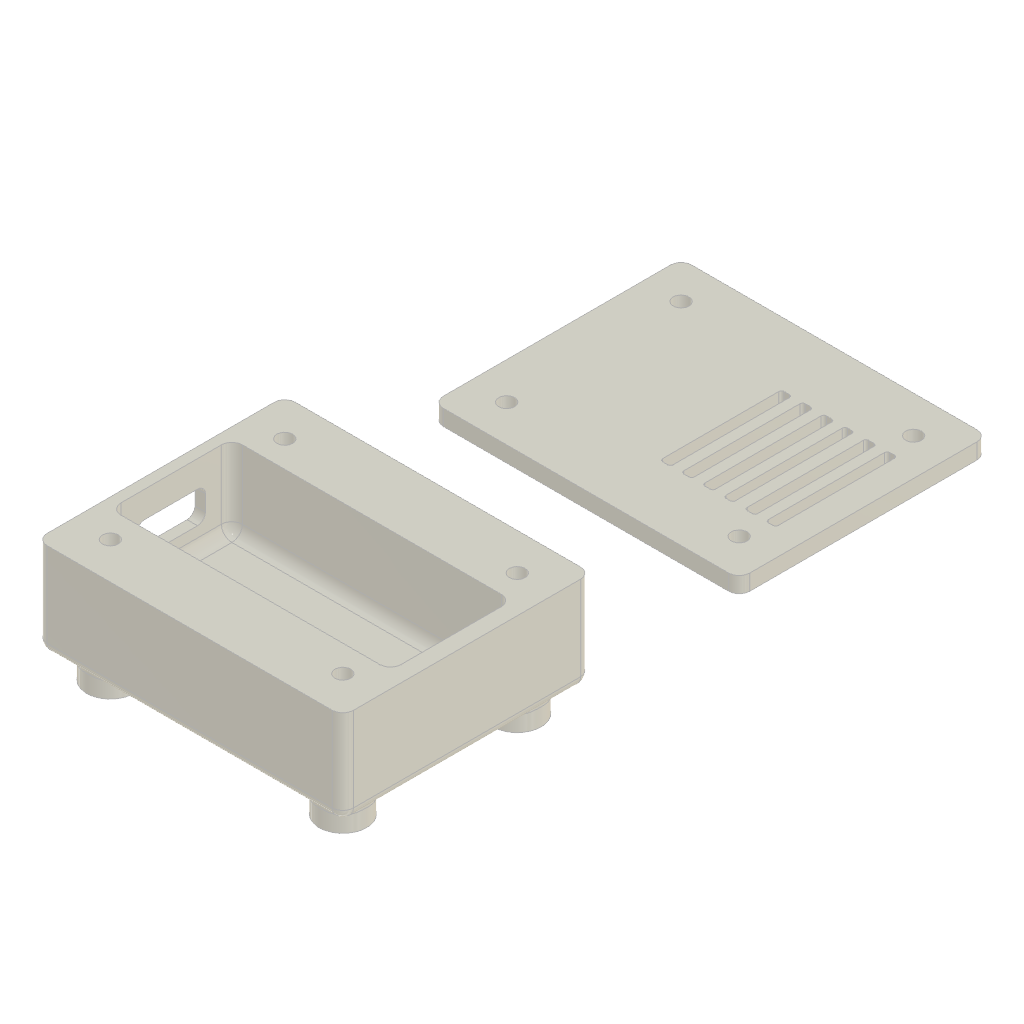
transmitter (Autodesk Fusion 360 design; units mm, degrees)
part number: 2026-10-18-01-48-49-370
Autodesk Fusion 360 part; units mm, degrees
sketch "Sketch1" plane through (0, 0, 0) normal (0, 0, 1) x (1, 0, 0)
  line L0 (20, 50) -> (73, 50)
  line L1 (73, 50) -> (73, 27)
  line L2 (73, 27) -> (20, 27)
  line L3 (20, 27) -> (20, 50)
  line L4 (20, 27) -> (20, 32) construction
  line L5 (20, 50) -> (20, 45) construction
  line L6 (20, 45) -> (18, 45)
  line L7 (18, 45) -> (18, 32)
  line L8 (18, 32) -> (20, 32)
  line L9 (20, 32) -> (20, 45)
  circle A0 centre (25, 55) radius 4.5
  circle A1 centre (25, 55) radius 3
  circle A2 centre (25, 55) radius 1.5
  line L10 (25, 55) -> (25, 50) construction
  line L11 (25, 27) -> (25, 22) construction
  line L12 (69, 50) -> (69, 55) construction
  line L13 (69, 27) -> (69, 22) construction
  circle A3 centre (69, 55) radius 1.5
  circle A4 centre (69, 55) radius 3
  circle A5 centre (69, 55) radius 4.5
  circle A6 centre (25, 22) radius 1.5
  circle A7 centre (69, 22) radius 1.5
  circle A8 centre (69, 22) radius 3
  circle A9 centre (69, 22) radius 4.5
  circle A10 centre (25, 22) radius 3
  circle A11 centre (25, 22) radius 4.5
  line L14 (18, 15) -> (76, 15)
  line L15 (76, 15) -> (76, 62)
  line L16 (76, 62) -> (18, 62)
  line L17 (18, 62) -> (18, 15)
  line L18 (73, 50) -> (70.8894, 50)
  line L19 (70.8894, 50) -> (70.8894, 27)
  line L20 (70.8894, 27) -> (73, 27)
  line L21 (73, 27) -> (73, 50)
  line L22 (70.8894, 27) -> (69, 27)
  line L23 (69, 27) -> (69, 50)
  line L24 (69, 50) -> (70.8894, 50)
  line L25 (70.8894, 50) -> (70.8894, 27)
  line L26 (69, 27) -> (67, 27)
  line L27 (67, 27) -> (67, 50)
  line L28 (67, 50) -> (69, 50)
  line L29 (69, 50) -> (69, 27)
  line L30 (67, 50) -> (65, 50)
  line L31 (65, 50) -> (65, 27)
  line L32 (65, 27) -> (67, 27)
  line L33 (67, 27) -> (67, 50)
  line L34 (65, 27) -> (62.7927, 27)
  line L35 (62.7927, 27) -> (62.7927, 50)
  line L36 (62.7927, 50) -> (65, 50)
  line L37 (65, 50) -> (65, 27)
  line L38 (62.7927, 50) -> (61, 50)
  line L39 (61, 50) -> (61, 27)
  line L40 (61, 27) -> (62.7927, 27)
  line L41 (62.7927, 27) -> (62.7927, 50)
  line L42 (61, 27) -> (59, 27)
  line L43 (59, 27) -> (59, 50)
  line L44 (59, 50) -> (61, 50)
  line L45 (61, 50) -> (61, 27)
  line L46 (59, 50) -> (57, 50)
  line L47 (57, 50) -> (57, 27)
  line L48 (57, 27) -> (59, 27)
  line L49 (59, 27) -> (59, 50)
  line L50 (57, 27) -> (55, 27)
  line L51 (55, 27) -> (55, 50)
  line L52 (55, 50) -> (57, 50)
  line L53 (57, 50) -> (57, 27)
  line L54 (55, 27) -> (53, 27)
  line L55 (53, 27) -> (53, 50)
  line L56 (53, 50) -> (55, 50)
  line L57 (55, 50) -> (55, 27)
  line L58 (53, 27) -> (51, 27)
  line L59 (51, 27) -> (51, 50)
  line L60 (51, 50) -> (53, 50)
  line L61 (53, 50) -> (53, 27)
  line L62 (51, 27) -> (49, 27)
  line L63 (49, 27) -> (49, 50)
  line L64 (49, 50) -> (51, 50)
  line L65 (51, 50) -> (51, 27)
  line L66 (25, 102) -> (25, 97) construction
  circle A12 centre (25, 97) radius 3
  line L67 (18, 137) -> (18, 90)
  line L68 (18, 120) -> (18, 107)
  circle A13 centre (25, 130) radius 3
  circle A14 centre (25, 130) radius 4.5
  circle A15 centre (25, 130) radius 1.5
  line L69 (18, 90) -> (76, 90)
  line L70 (18, 107) -> (20, 107)
  line L71 (20, 102) -> (20, 125)
  line L72 (20, 120) -> (18, 120)
  line L73 (20, 107) -> (20, 120)
  circle A16 centre (25, 97) radius 4.5
  line L74 (20, 125) -> (20, 120) construction
  line L75 (76, 137) -> (18, 137)
  circle A17 centre (25, 97) radius 1.5
  line L76 (20, 125) -> (73, 125)
  line L77 (73, 102) -> (20, 102)
  line L78 (25, 130) -> (25, 125) construction
  line L79 (73, 125) -> (70.8894, 125)
  line L80 (62.7927, 102) -> (62.7927, 125)
  line L81 (20, 102) -> (20, 107) construction
  circle A18 centre (69, 130) radius 4.5
  line L82 (67, 125) -> (69, 125)
  line L83 (69, 125) -> (69, 130) construction
  line L84 (51, 102) -> (51, 125)
  line L85 (57, 125) -> (57, 102)
  circle A19 centre (69, 130) radius 1.5
  line L86 (67, 102) -> (67, 125)
  circle A20 centre (69, 130) radius 3
  line L87 (62.7927, 125) -> (65, 125)
  line L88 (59, 102) -> (59, 125)
  line L89 (49, 102) -> (49, 125)
  line L90 (55, 102) -> (55, 125)
  line L91 (51, 125) -> (51, 102)
  line L92 (76, 90) -> (76, 137)
  line L93 (65, 102) -> (67, 102)
  line L94 (67, 125) -> (65, 125)
  line L95 (57, 102) -> (55, 102)
  circle A21 centre (69, 97) radius 1.5
  line L96 (73, 102) -> (73, 125)
  line L97 (65, 125) -> (65, 102)
  line L98 (69, 102) -> (67, 102)
  line L99 (69, 125) -> (70.8894, 125)
  circle A22 centre (69, 97) radius 4.5
  line L100 (55, 125) -> (57, 125)
  circle A23 centre (69, 97) radius 3
  line L101 (59, 125) -> (57, 125)
  line L102 (51, 125) -> (53, 125)
  line L103 (70.8894, 102) -> (69, 102)
  line L104 (53, 125) -> (53, 102)
  line L105 (55, 102) -> (53, 102)
  line L106 (61, 102) -> (59, 102)
  line L107 (49, 125) -> (51, 125)
  line L108 (70.8894, 125) -> (70.8894, 102)
  line L109 (65, 102) -> (62.7927, 102)
  line L110 (59, 125) -> (61, 125)
  line L111 (67, 102) -> (67, 125)
  line L112 (51, 102) -> (49, 102)
  line L113 (53, 125) -> (55, 125)
  line L114 (53, 102) -> (51, 102)
  line L115 (69, 102) -> (69, 125)
  line L116 (57, 102) -> (59, 102)
  line L117 (69, 125) -> (69, 102)
  line L118 (62.7927, 125) -> (61, 125)
  line L119 (61, 125) -> (61, 102)
  line L120 (61, 102) -> (62.7927, 102)
  line L121 (70.8894, 102) -> (73, 102)
  line L122 (59, 102) -> (59, 125)
  line L123 (55, 125) -> (55, 102)
  line L124 (73, 125) -> (73, 102)
  line L125 (69, 102) -> (69, 97) construction
  line L126 (70.8894, 125) -> (70.8894, 102)
  line L127 (65, 125) -> (65, 102)
  line L128 (53, 102) -> (53, 125)
  line L129 (62.7927, 102) -> (62.7927, 125)
  line L130 (57, 125) -> (57, 102)
  line L131 (61, 125) -> (61, 102)
  dimension "d1" = 53
  dimension "d2" = 23
  dimension "d3" = 5
  dimension "d4" = 5
  dimension "d5" = 9
  dimension "d6" = 6
  dimension "d7" = 3
  dimension "d8" = 5
  dimension "d9" = 5
  dimension "d10" = 5
  dimension "d11" = 3
  dimension "d12" = 6
  dimension "d13" = 9
  dimension "d14" = 3
  dimension "d15" = 3
  dimension "d16" = 6
  dimension "d17" = 9
  dimension "d18" = 6
  dimension "d19" = 9
  dimension "d20" = 53
  dimension "d21" = 23
  dimension "d22" = 5
  dimension "d23" = 5
  dimension "d24" = 9
  dimension "d25" = 6
  dimension "d26" = 3
  dimension "d27" = 5
  dimension "d28" = 5
  dimension "d29" = 5
  dimension "d30" = 3
  dimension "d31" = 6
  dimension "d32" = 9
  dimension "d33" = 3
  dimension "d34" = 3
  dimension "d35" = 6
  dimension "d36" = 9
  dimension "d37" = 6
  dimension "d38" = 9
  constraint horizontal L0
  constraint vertical L1
  constraint horizontal L2
  constraint vertical L3
  constraint perpendicular L2 L4
  constraint perpendicular L0 L5
  constraint horizontal L6
  constraint vertical L7
  constraint horizontal L8
  constraint vertical L9
  constraint concentric A0 A1
  constraint concentric A1 A2
  constraint coincident A0.centre A1.centre
  constraint coincident L0 L10.end
  constraint perpendicular L0 L10
  constraint coincident L2 L11.start
  constraint perpendicular L2 L11
  constraint coincident L0 L12.start
  constraint perpendicular L0 L12
  constraint coincident L2 L13.start
  constraint perpendicular L2 L13
  constraint coincident L12.end A3.centre
  constraint concentric A3 A4
  constraint concentric A4 A5
  constraint coincident L11.end A6.centre
  constraint coincident L13.end A7.centre
  constraint concentric A7 A8
  constraint concentric A7 A9
  constraint concentric A6 A10
  constraint concentric A6 A11
  constraint horizontal L14
  constraint vertical L15
  constraint horizontal L16
  constraint vertical L17
  constraint horizontal L18
  constraint vertical L19
  constraint horizontal L20
  constraint vertical L21
  constraint coincident L2 L19.end
  constraint horizontal L22
  constraint vertical L23
  constraint horizontal L24
  constraint vertical L25
  constraint horizontal L26
  constraint vertical L27
  constraint horizontal L28
  constraint vertical L29
  constraint coincident L0 L27.end
  constraint horizontal L30
  constraint vertical L31
  constraint horizontal L32
  constraint vertical L33
  constraint coincident L2 L31.end
  constraint horizontal L34
  constraint vertical L35
  constraint horizontal L36
  constraint vertical L37
  constraint coincident L0 L35.end
  constraint horizontal L38
  constraint vertical L39
  constraint horizontal L40
  constraint vertical L41
  constraint coincident L2 L39.end
  constraint horizontal L42
  constraint vertical L43
  constraint horizontal L44
  constraint vertical L45
  constraint coincident L0 L43.end
  constraint horizontal L46
  constraint vertical L47
  constraint horizontal L48
  constraint vertical L49
  constraint coincident L2 L47.end
  constraint horizontal L50
  constraint vertical L51
  constraint horizontal L52
  constraint vertical L53
  constraint coincident L0 L51.end
  constraint horizontal L54
  constraint vertical L55
  constraint horizontal L56
  constraint vertical L57
  constraint coincident L0 L55.end
  constraint horizontal L58
  constraint vertical L59
  constraint horizontal L60
  constraint vertical L61
  constraint coincident L0 L59.end
  constraint horizontal L62
  constraint vertical L63
  constraint horizontal L64
  constraint vertical L65
  constraint coincident L0 L63.end
  constraint horizontal L76
  constraint vertical L124
  constraint horizontal L77
  constraint vertical L71
  constraint perpendicular L77 L81
  constraint perpendicular L74 L76
  constraint horizontal L72
  constraint vertical L68
  constraint horizontal L70
  constraint vertical L73
  constraint concentric A13 A14
  constraint concentric A13 A15
  constraint coincident A13.centre A14.centre
  constraint coincident L78.end L76
  constraint perpendicular L76 L78
  constraint coincident L66.start L77
  constraint perpendicular L66 L77
  constraint coincident L82.end L76
  constraint perpendicular L76 L83
  constraint coincident L98.start L77
  constraint perpendicular L77 L125
  constraint coincident A18.centre L83.end
  constraint concentric A19 A20
  constraint concentric A18 A20
  constraint coincident L66.end A12.centre
  constraint coincident A21.centre A22.centre
  constraint concentric A21 A23
  constraint concentric A21 A22
  constraint concentric A12 A17
  constraint concentric A16 A17
  constraint horizontal L69
  constraint vertical L92
  constraint horizontal L75
  constraint vertical L67
  constraint horizontal L79
  constraint vertical L108
  constraint horizontal L121
  constraint vertical L96
  constraint coincident L103.start L77
  constraint horizontal L103
  constraint vertical L115
  constraint horizontal L99
  constraint vertical L126
  constraint horizontal L98
  constraint vertical L86
  constraint horizontal L82
  constraint vertical L117
  constraint coincident L82.start L76
  constraint horizontal L94
  constraint vertical L127
  constraint horizontal L93
  constraint vertical L111
  constraint coincident L93.start L77
  constraint horizontal L109
  constraint vertical L80
  constraint horizontal L87
  constraint vertical L97
  constraint coincident L80.end L76
  constraint horizontal L118
  constraint vertical L119
  constraint horizontal L120
  constraint vertical L129
  constraint coincident L106.start L77
  constraint horizontal L106
  constraint vertical L88
  constraint horizontal L110
  constraint vertical L131
  constraint coincident L88.end L76
  constraint horizontal L101
  constraint vertical L130
  constraint horizontal L116
  constraint vertical L122
  constraint coincident L85.end L77
  constraint horizontal L95
  constraint vertical L90
  constraint horizontal L100
  constraint vertical L85
  constraint coincident L90.end L76
  constraint horizontal L105
  constraint vertical L128
  constraint horizontal L113
  constraint vertical L123
  constraint coincident L102.end L76
  constraint horizontal L114
  constraint vertical L84
  constraint horizontal L102
  constraint vertical L104
  constraint coincident L84.end L76
  constraint horizontal L112
  constraint vertical L89
  constraint horizontal L107
  constraint vertical L91
  constraint coincident L89.end L76
  measures "d1" distance of L0.start L0.end
  measures "d2" distance of L0.start L2.end
  measures "d3" distance of L2.end L4.end
  measures "d4" distance of L0.start L5.end
  measures "d5" diameter of A0
  measures "d6" diameter of A1
  measures "d7" diameter of A2
  measures "d8" distance of L11.start L11.end
  measures "d9" distance of L12.start L12.end
  measures "d10" distance of L13.start L13.end
  measures "d11" diameter of A3
  measures "d12" diameter of A4
  measures "d13" diameter of A5
  measures "d14" diameter of A6
  measures "d15" diameter of A7
  measures "d16" diameter of A8
  measures "d17" diameter of A9
  measures "d18" diameter of A10
  measures "d19" diameter of A11
  measures "d20" distance of L76.end L71.end
  measures "d21" distance of L71.end L71.start
  measures "d22" distance of L71.start L70.end
  measures "d23" distance of L71.end L72.start
  measures "d24" diameter of A14
  measures "d25" diameter of A13
  measures "d26" diameter of A15
  measures "d27" distance of L66.end L66.start
  measures "d28" distance of L82.end A18.centre
  measures "d29" distance of A21.centre L98.start
  measures "d30" diameter of A19
  measures "d31" diameter of A20
  measures "d32" diameter of A18
  measures "d33" diameter of A17
  measures "d34" diameter of A21
  measures "d35" diameter of A23
  measures "d36" diameter of A22
  measures "d37" diameter of A12
  measures "d38" diameter of A16
extrude "Extrude1" add sketch "Sketch1" along normal blind 18 contours L0 L1 L2 L3 L6 L8 L14 L15 L16 L17 L18 L20 L21 L22 L24 L26 L28 L30 L32 L34 L36 L38 L40 L42 L44 L46 L48 L50 L52 L54 L56 L58 L60 L62 L64 | A0 | A1 | A4 | A5 | A8 | A9 | A10 | A11 makes body 1
extrude "Extrude2" add sketch "Sketch1" along normal blind 3 contours L0 L2 L3 L9 L63 | L0 L2 L59 L62 L63 L64 L65 | L0 L2 L55 L58 L59 L60 L61 L65 | L0 L2 L51 L54 L55 L56 L57 L61 | L0 L2 L47 L50 L51 L52 L53 L57 | L0 L2 L43 L46 L47 L48 L49 L53 | L0 L2 L39 L42 L43 L44 L45 L49 | L0 L2 L35 L38 L39 L40 L41 L45 | L0 L2 L31 L34 L35 L36 L37 L41 | L0 L2 L27 L30 L31 L32 L33 L37 | L0 L2 L23 L26 L27 L28 L29 L33 | L0 L2 L19 L22 L23 L24 L25 L29 | L0 L1 L2 L18 L19 L20 L21 L25 bodies 1
extrude "Extrude3" add sketch "Sketch1" along normal blind 7 contours L3 L6 L7 L8 L9 L17 bodies 1
extrude "Extrude4" add 1 faces at (18.6667, 40.6667, 7) along direction (0, 0, 1) blind 5 from surface at 6 on bodies 1 bodies 1
extrude "Extrude5" add sketch "Sketch1" against normal blind 5 contours A0 | A5 | A9 | A11 bodies 1
extrude "Extrude6" add sketch "Sketch1" along normal blind 3 separate body contours A12 | L67 L69 L70 L71 L72 L75 L76 L77 L79 L82 L87 L92 L93 L94 L95 L96 L98 L99 L100 L101 L102 L103 L105 L106 L107 L109 L110 L112 L113 L114 L116 L118 L120 L121 L124 | L67 L68 L70 L71 L72 L73 | L71 L73 L76 L77 L89 | L76 L77 L84 L91 L102 L104 L114 L128 | L76 L77 L85 L90 L95 L100 L123 L130 | L76 L77 L88 L106 L110 L119 L122 L131 | L76 L77 L80 L87 L97 L109 L127 L129 | L76 L77 L82 L86 L98 L111 L115 L117 | L76 L77 L79 L96 L108 L121 L124 L126 | A13 | A14 | A16 | A18 | A20 | A22 | A23 makes body 2
extrude "Extrude7" add sketch "Sketch1" against normal blind 2 contours A14 | A16 | A18 | A22 bodies 2
fillet "Fillet1" radius 1.5 4 edges at (19, 32, 7) (19, 45, 7) (19, 45, 13) (19, 32, 13) on bodies 1
fillet "Fillet3" radius 0.5 24 edges at (70.8894, 102, 1.5) (69, 102, 1.5) (69, 125, 1.5) (70.8894, 125, 1.5) (67, 102, 1.5) (65, 102, 1.5) (65, 125, 1.5) (67, 125, 1.5) (62.7927, 125, 1.5) (61, 125, 1.5) (61, 102, 1.5) (62.7927, 102, 1.5) (59, 102, 1.5) (57, 102, 1.5) (57, 125, 1.5) (59, 125, 1.5) (55, 125, 1.5) (53, 125, 1.5) (49, 125, 1.5) (51, 125, 1.5) (49, 102, 1.5) (51, 102, 1.5) (53, 102, 1.5) (55, 102, 1.5) on bodies 2
fillet "Fillet2" radius 2 32 edges at (20, 27, 10.5) (20, 50, 10.5) (73, 50, 10.5) (73, 27, 10.5) (20, 38.5, 3) (46.5, 27, 3) (46.5, 50, 3) (73, 38.5, 3) (76, 15, 9) (76, 62, 9) (18, 62, 9) (18, 15, 9) (47, 15, 0) (76, 38.5, 0) (47, 62, 0) (18, 38.5, 0) (64.8045, 53.3727, 0) (20.8045, 53.3727, 0) (20.8045, 20.3727, 0) (64.8045, 20.3727, 0) (76, 137, 1.5) (76, 90, 1.5) (18, 137, 1.5) (18, 90, 1.5) (20.8045, 95.3727, 0) (20.8045, 128.3727, 0) (22.203, 131.0848, 0) (22.203, 98.0848, 0) (66.203, 98.0848, 0) (66.203, 131.0848, 0) (64.8045, 128.3727, 0) (64.8045, 95.3727, 0) on bodies 1 2
